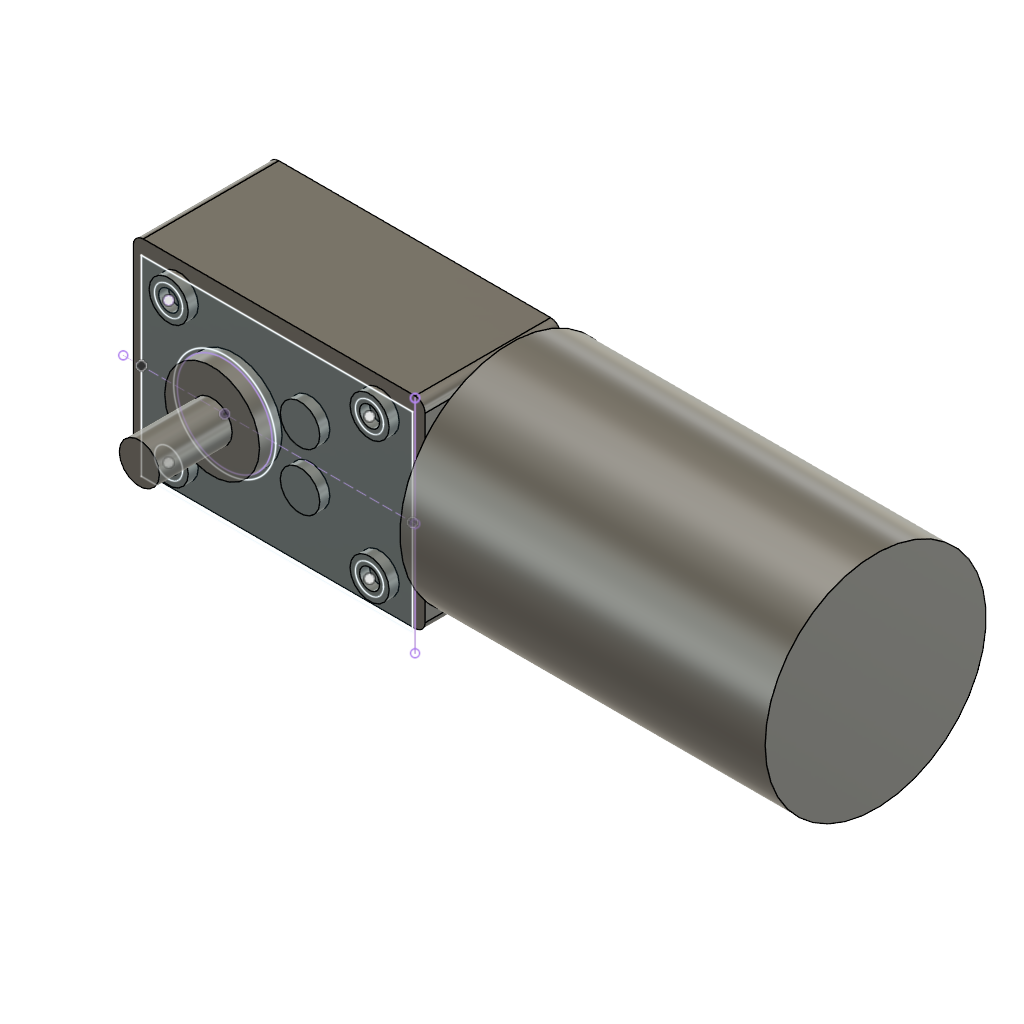
TS-40GZ (Autodesk Fusion 360 design; units mm, degrees)
Autodesk Fusion 360 part; units mm, degrees
sketch "Sketch1" plane through (0, 0, 0) normal (0, 0, 1) x (1, 0, 0)
  line L0 (-18.2, 20.06) -> (35.9, 20.06)
  line L1 (37.9, 18.06) -> (37.9, -18.06)
  line L2 (35.9, -20.06) -> (-18.2, -20.06)
  line L3 (-20.2, -18.06) -> (-20.2, 18.06)
  circle A0 centre (0, 0) radius 9.4361
  circle A1 centre (0, 0) radius 4
  circle A2 centre (15, 5.7) radius 3.937
  circle A3 centre (28.85, 14) radius 3.9
  circle A4 centre (28.85, 14) radius 2
  line L4 (8.85, 20.06) -> (8.85, -20.06) construction
  line L5 (-20.2, 0) -> (37.9, 0) construction
  circle A5 centre (28.85, -14) radius 3.9
  circle A6 centre (28.85, -14) radius 2
  circle A7 centre (-11.15, 14) radius 3.9
  circle A8 centre (-11.15, 14) radius 2
  circle A9 centre (-11.15, -14) radius 3.9
  circle A10 centre (-11.15, -14) radius 2
  circle A11 centre (15, -5.7) radius 3.937
  arc A12 (-18.2, 20.06) -> (-20.2, 18.06) centre (-18.2, 18.06) ccw
  arc A13 (37.9, 18.06) -> (35.9, 20.06) centre (35.9, 18.06) ccw
  arc A14 (35.9, -20.06) -> (37.9, -18.06) centre (35.9, -18.06) ccw
  arc A15 (-20.2, -18.06) -> (-18.2, -20.06) centre (-18.2, -18.06) ccw
  circle A16 centre (-17.7, 17.56) radius 1
  circle A17 centre (35.4, 17.56) radius 1
  circle A18 centre (35.4, -17.56) radius 1
  circle A19 centre (-17.7, -17.56) radius 1
  point P0 (-20.2, 20.06)
  point P1 (37.9, 20.06)
  point P2 (37.9, -20.06)
  point P3 (8.85, 20.06)
  point P4 (-20.2, 0)
  point P5 (15, 0)
  point P6 (37.9, 0)
  point P7 (-20.2, 0)
  dimension "d1" = 58.1
  dimension "d2" = 40.12
  dimension "d3" = 8
  dimension "d4" = 18.8722
  dimension "d5" = 37.9
  dimension "d6" = 7.874
  dimension "d7" = 15
  dimension "d8" = 4
  dimension "d9" = 7.8
  dimension "d10" = 20
  dimension "d11" = 14
  dimension "d12" = 5.7
  dimension "d13" = 2
  dimension "d14" = 2
  dimension "d15" = 17.56
  dimension "d16" = 2.5
  constraint horizontal L0
  constraint vertical L1
  constraint horizontal L2
  constraint vertical L3
  constraint coincident A0.centre A1.centre
  constraint concentric A0 A1
  constraint horizontal A0.centre P4
  constraint horizontal A0.centre P5
  constraint concentric A3 A4
  constraint coincident P3 L4.start
  constraint coincident P4 L5.start
  constraint symmetric A3 L5 A5
  constraint symmetric A4 L5 A6
  constraint symmetric A3 L4 A7
  constraint symmetric A4 L4 A8
  constraint symmetric L4 A5 A9
  constraint symmetric L4 A6 A10
  constraint symmetric A2 L5 A11
  constraint coincident L3 P4
  constraint coincident P0 L3
  constraint coincident L0 P3
  constraint coincident P0 L0
  constraint tangent L3 A12
  constraint tangent L0 A12
  constraint coincident P1 L0
  constraint coincident L1 P6
  constraint coincident P1 L1
  constraint tangent L0 A13
  constraint tangent L1 A13
  constraint equal A12 A13
  constraint coincident P2 L1
  constraint coincident L2 L4.end
  constraint coincident P2 L2
  constraint tangent L1 A14
  constraint tangent L2 A14
  constraint equal A12 A14
  constraint tangent L2 A15
  constraint tangent L3 A15
  constraint equal A12 A15
  constraint midpoint L1 P6
  constraint midpoint L3 P7
  constraint coincident L5 P7
  constraint symmetric L4 A16 A17
  constraint symmetric L5 A16 A19
  constraint symmetric L5 A17 A18
  measures "d1" horizontal distance of P0 P1
  measures "d2" vertical distance of P1 P2
  measures "d3" diameter of A1
  measures "d4" diameter of A0
  measures "d5" distance of L1 A0.centre
  measures "d6" diameter of A2
  measures "d7" horizontal distance of A0.centre A2.centre
  measures "d8" diameter of A4
  measures "d9" diameter of A3
  measures "d10" distance of A3.centre L4
  measures "d11" distance of A3.centre L5
  measures "d12" distance of A2.centre L5
  measures "d13" radius of A12
  measures "d14" diameter of A16
  measures "d15" distance of L5 A16.centre
  measures "d16" distance of L3 A16.centre
extrude "Extrude1" add sketch "Sketch1" against normal blind 27 contours L0 L1 L2 L3 A12 A13 A14 A15 | A0 | A1 | A2 | A3 | A4 | A5 | A6 | A7 | A8 | A9 | A10 | A11 | A16 | A17 | A18 | A19 makes body 1
extrude "Extrude2" add sketch "Sketch1" along normal blind 19 separate body contours A1 makes body 2
extrude "Extrude3" add sketch "Sketch1" along normal blind 4.5 contours A0 bodies 1 2
extrude "Extrude4" add sketch "Sketch1" along normal blind 2 contours A2 | A3 | A5 | A7 | A9 | A11 bodies 1
sketch "Sketch2" plane through (37.9, 0, 0) normal (1, 0, 0) x (0, 0, -1)
  line L0 (0, 18.06) -> (0, -18.06)
  line L1 (0, -18.06) -> (27, -18.06)
  line L2 (27, -18.06) -> (27, 18.06)
  line L3 (27, 18.06) -> (0, 18.06)
  line L4 (0, 20.06) -> (27, 20.06)
  line L5 (0, -20.06) -> (27, -20.06)
  line L6 (13.5, 20.06) -> (13.5, -20.06) construction
  circle A0 centre (16.9978, -0.3096) radius 22
  point P0 (13.5, 20.06)
  point P1 (13.5, -20.06)
  point P2 (-5, 0)
  dimension "d25" = 44
  dimension "d29" = 5
  constraint midpoint P0 L4
  constraint midpoint P1 L5
  constraint coincident P0 L6.start
  constraint coincident P1 L6.end
  constraint coincident A0 P2
  constraint horizontal origin P2
  measures "d25" diameter of A0
  measures "d29" distance of P2 origin
extrude "Extrude5" add sketch "Sketch2" along normal blind 72.7 contours L0 L1 L2 L3 A0 | L0 A0 | L1 L2 L3 L4 L5 A0 | L4 A0 | L5 A0 bodies 1
copy_body "Body->Comp2" bodies 1 removing the originals makes body 3 in component "Motor"
sketch "Sketch2 (2)" plane through (0, 0, 2) normal (0, 0, 1) x (1, 0, 0) in component "Motor Spacer"
  circle A0 centre (-11.15, 14) radius 2
  line L0 (-16.583, 19.05) -> (37.392, 19.05)
  line L1 (37.392, 19.05) -> (37.392, -19.05)
  line L2 (37.392, -19.05) -> (-16.583, -19.05)
  line L3 (-16.583, -19.05) -> (-16.583, 19.05)
  line L4 (37.9, -22.3096) -> (37.9, 21.6904)
  circle A1 centre (28.85, 14) radius 2.794
  circle A2 centre (-11.15, -14) radius 2.794
  circle A3 centre (28.85, -14) radius 2.794
  circle A4 centre (0, 0) radius 10.16
  line L5 (-20.2, 0) -> (37.9, 0) construction
  circle A5 centre (0, 0) radius 9.4361
  circle A6 centre (-11.15, 14) radius 2.794
  point P0 (-16.583, 0)
  point P1 (37.392, 0)
  dimension "d30" = 0.508
  dimension "d31" = 53.975
  dimension "d32" = 38.1
  dimension "d36" = 40
  dimension "d37" = -28
  dimension "d45" = 20.32
  dimension "d46" = 5.588
  constraint horizontal L0
  constraint vertical L1
  constraint horizontal L2
  constraint vertical L3
  constraint midpoint L3 P0
  constraint midpoint L1 P1
  constraint horizontal A4.centre P0
  constraint coincident A4.centre A5.centre
  constraint concentric A0 A6
  measures "d30" distance of L1 L4
  measures "d31" horizontal distance of L0.start L0.end
  measures "d32" vertical distance of L0.start L2.end
  measures "d45" diameter of A4
  measures "d46" diameter of A6
extrude "Extrude1'" [suppressed] in component "Motor Spacer"
component "Motor Spacer" placed x (1, 0, 0) y (0, 1, 0) z (0, 0, 1) at (0, 0, 0)
component "Motor" placed x (1, 0, 0) y (0, 1, 0) z (0, 0, 1) at (0, 0, 0)
